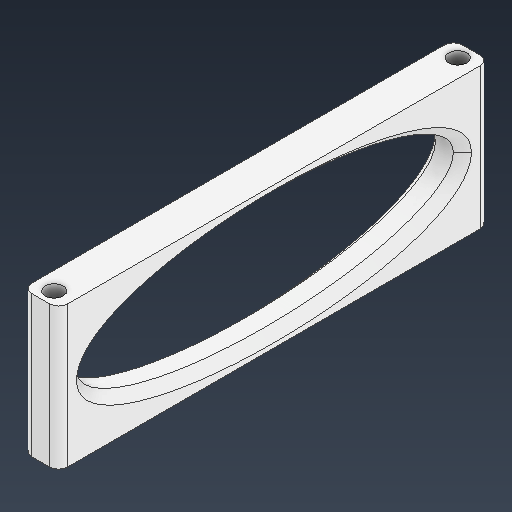
# Autodesk Inventor part: side
Saved by Autodesk Inventor 2026.2 (Build 302298010, 298A)
## iProperties
Created: 2026-04-10
Part Number: side
Material: PLA
Document SubType Name: Modeling
Designer: khw
Density: 1.24 g/cm^3
Appearance: 일반
Author: khw
Autodesk Inventor part; units mm, degrees
ref_plane "YZ Plane" through (0, 0, 0) normal (1, 0, 0) x (0, 1, 0)
ref_plane "XZ Plane" through (0, 0, 0) normal (0, 1, 0) x (-1, 0, 0)
ref_plane "XY Plane" through (0, 0, 0) normal (0, 0, 1) x (1, 0, 0)
sketch "스케치1" plane through (0, 0, 0) normal (1, 0, 0) x (0, 1, 0)
  line L0 (0, 0) -> (31.5, 0) construction
  line L1 (31.5, 0) -> (31.5, -90) construction
  line L2 (31.5, -90) -> (0, -90) construction
  line L3 (0, -90) -> (0, 0) construction
  line L4 (31.5, 3) -> (0, 3)
  line L5 (0, 3) -> (0, -93)
  line L6 (0, -93) -> (31.5, -93)
  line L7 (31.5, -93) -> (31.5, 3)
  line L8 (31.5, -45) -> (0, -45) construction
  line L9 (15.75, 3) -> (15.75, -93) construction
  ellipse E0 centre (15.75, -45) end of major axis (15.75, -87) minor radius 12.75
  point P0 (28.5, -45)
  point P1 (15.75, -87)
  point P2 (15.75, -90)
  dimension "d0" = 31.5
  dimension "d1" = 90
  dimension "d2" = 96
  dimension "d3" = 3
  dimension "d4" = 3
  constraints: 20 end point, 8 midpoint, 4 parallel, 4 perpendicular, 2 horizontal, 2 point on line, 4 other
  measures "d0" distance of L1.end L2.end
  measures "d1" distance of L0.end L1.end
  measures "d2" distance from line of L9.end L4
  measures "d3" distance of L8.start point (28.5, -45)
  measures "d4" distance of point (15.75, -90) point (15.75, -87)
extrude "돌출1" add sketch "스케치1" along normal mid plane 8
sketch "스케치2" plane through (-4, 31.5, 3) normal (0, 1, 0) x (1, 0, 0)
  line L0 (4, 3) -> (4, 93) construction
  dimension "d7" = 90
  constraints: 2 coincident, 2 end point, 1 vertical
  measures "d7" distance of L0.start L0.end
hole "구멍1" at (0, 31.5, 0) at (0, 31.5, -90) direction (0, -1, 0) diameter 4 end through all
chamfer "모따기1" distance 2 angle 45 2 edges at (4, 15.75, -3) (-4, 15.75, -3)
fillet "모깎기1" radius 2 4 edges at (-4, 15.75, 3) (4, 15.75, 3) (4, 15.75, -93) (-4, 15.75, -93)
